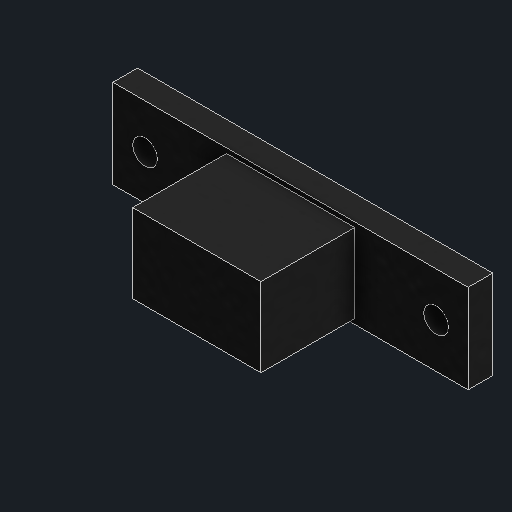
# Autodesk Inventor part: usb_microB_panel_socket
Saved by Autodesk Inventor 2027.1 (Build 311270010, 270A)
## iProperties
Created: 2026-10-29
Part Number: usb_microB_panel_socket
Material: Generic
Document SubType Name: Modeling
Designer: alexg
Density: 1 g/cm^3
Appearance: Black
Description: Micro-B panel extender socket v2: measured ear holes 2.5 dia (no thread) at 29.5 pitch; ear plate 36 long is an estimate
Mass: 1.66471 g
Surface Area: 14.0763 cm^2
Volume: 1.66471 cm^3
Author: alexg
Autodesk Inventor part; units mm, degrees
ref_plane "Work Plane1" through (0, 0, -24.8) normal (0, 0, 1) x (1, 0, 0)
sketch "Ear plate sketch" plane through (0, 0, -24.8) normal (0, 0, 1) x (1, 0, 0)
  line L0 (-39, -30.34) -> (-9, -30.34)
  line L1 (-9, -30.34) -> (-9, -21.34)
  line L2 (-9, -21.34) -> (-39, -21.34)
  line L3 (-39, -21.34) -> (-39, -30.34)
  constraints: 8 end point, 2 parallel, 1 horizontal, 1 perpendicular
extrude "Ear plate" add sketch "Ear plate sketch" along normal blind 2.5
ref_plane "Work Plane2" through (0, 0, -22.3) normal (0, 0, 1) x (1, 0, 0)
sketch "Ear holes sketch" plane through (0, 0, -22.3) normal (0, 0, 1) x (1, 0, 0)
  circle A0 centre (-36.5, -25.84) radius 1.35
  circle A1 centre (-11.5, -25.84) radius 1.35
  constraints: 2 centre point
extrude "Ear holes" [suppressed]
ref_plane "Work Plane3" through (0, 0, -24.8) normal (0, 0, 1) x (1, 0, 0)
sketch "Block sketch" plane through (0, 0, -24.8) normal (0, 0, 1) x (1, 0, 0)
  line L0 (-30.5, -29.84) -> (-17.5, -29.84)
  line L1 (-17.5, -29.84) -> (-17.5, -21.84)
  line L2 (-17.5, -21.84) -> (-30.5, -21.84)
  line L3 (-30.5, -21.84) -> (-30.5, -29.84)
  constraints: 8 end point, 2 parallel, 1 horizontal, 1 perpendicular
extrude "Block" add sketch "Block sketch" along normal blind 12
ref_plane "Work Plane4" through (0, 0, -24.8) normal (0, 0, 1) x (1, 0, 0)
sketch "Micro-B opening sketch" plane through (0, 0, -24.8) normal (0, 0, 1) x (1, 0, 0)
  line L0 (-27.75, -27.09) -> (-20.25, -27.09)
  line L1 (-20.25, -27.09) -> (-20.25, -24.59)
  line L2 (-20.25, -24.59) -> (-27.75, -24.59)
  line L3 (-27.75, -24.59) -> (-27.75, -27.09)
  constraints: 8 end point, 2 parallel, 1 horizontal, 1 perpendicular
extrude "Micro-B opening" cut sketch "Micro-B opening sketch" along normal blind 5.8
ref_plane "Work Plane5" through (0, 0, -24.8) normal (0, 0, 1) x (1, 0, 0)
sketch "Ear plate widened to 36 (est.) sketch" plane through (0, 0, -24.8) normal (0, 0, 1) x (1, 0, 0)
  line L0 (-42, -30.34) -> (-39, -30.34)
  line L1 (-39, -30.34) -> (-39, -21.34)
  line L2 (-39, -21.34) -> (-42, -21.34)
  line L3 (-42, -21.34) -> (-42, -30.34)
  line L4 (-9, -30.34) -> (-6, -30.34)
  line L5 (-6, -30.34) -> (-6, -21.34)
  line L6 (-6, -21.34) -> (-9, -21.34)
  line L7 (-9, -21.34) -> (-9, -30.34)
  constraints: 16 end point, 4 parallel, 2 horizontal, 2 perpendicular
extrude "Ear plate widened to 36 (est.)" add sketch "Ear plate widened to 36 (est.) sketch" along normal blind 2.5
ref_plane "Work Plane6" through (0, 0, -24.8) normal (0, 0, 1) x (1, 0, 0)
sketch3d "Ear holes 2.5 at 29.5 pitch (measured: 32 outer-outer) sketc"
  constraints: 2 centre point
sketch "Ear holes 2.5 at 29.5 pitch (measured: 32 outer-outer) sketch" plane through (0, 0, -24.8) normal (0, 0, 1) x (1, 0, 0)
  circle A0 centre (-38.75, -25.84) radius 1.25
  circle A1 centre (-9.25, -25.84) radius 1.25
extrude "Ear holes 2.5 at 29.5 pitch (measured: 32 outer-outer)" cut sketch "Ear holes 2.5 at 29.5 pitch (measured: 32 outer-outer) sketch" along normal blind 2.5
body "Solid1"
